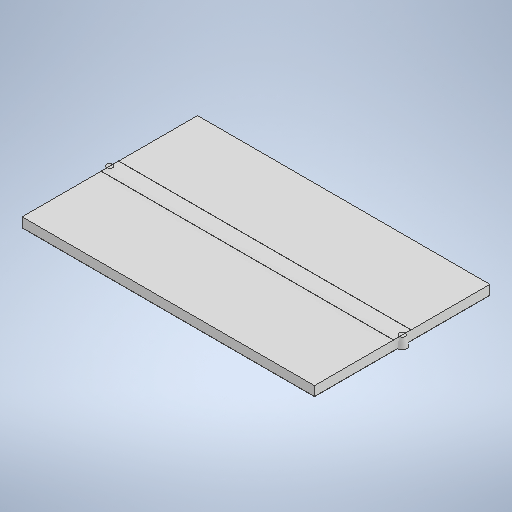
# Autodesk Inventor part: 01_linie50x30_3
Saved by Autodesk Inventor 2025.3 (Build 293356000, 356)
## iProperties
Created: 2026-10-16
Part Number: 01_linie50x30_3
Material: Generisch
Document SubType Name: Modeling
Designer: v.ivko
Density: 1 g/cm^3
Appearance: Vorgabe
Author: v.ivko
Autodesk Inventor part; units mm, degrees
ref_plane "YZ Plane" through (0, 0, 0) normal (1, 0, 0) x (0, 1, 0)
ref_plane "XZ Plane" through (0, 0, 0) normal (0, 1, 0) x (-1, 0, 0)
ref_plane "XY Plane" through (0, 0, 0) normal (0, 0, 1) x (1, 0, 0)
sketch "Skizze1" plane through (0, 0, 0) normal (0, 1, 0) x (-1, 0, 0)
  line L0 (-25, -15) -> (25, -15)
  line L1 (25, -15) -> (25, 15)
  line L2 (25, 15) -> (-25, 15)
  line L3 (-25, 15) -> (-25, -15)
  line L4 (-25, -15) -> (25, 15) construction
  line L5 (25, -15) -> (-25, 15) construction
  point P0 (0, 0)
  dimension "d0" = 50
  dimension "d1" = 30
  constraints: 12 end point, 2 midpoint, 2 parallel, 1 horizontal, 1 perpendicular
  measures "d0" distance of L1.end L2.end
  measures "d1" distance of L2.end L0.start
extrude "Extrusion1" add sketch "Skizze1" along normal blind 0.035
sketch "Skizze2" plane through (0, 0.035, 0) normal (0, 1, 0) x (1, 0, 0)
  line L0 (25, 15) -> (-25, 15) projected
  line L1 (25, -15) -> (-25, -15)
  line L2 (-25, -15) -> (-25, 15)
  line L3 (-25, 15) -> (25, 15)
  line L4 (25, 15) -> (25, -15)
  line L5 (25, -15) -> (-25, 15) construction
  line L6 (-25, -15) -> (25, 15) construction
  point P0 (0, 0)
  constraints: 12 end point, 2 midpoint, 2 parallel, 1 horizontal, 1 perpendicular
extrude "Extrusion2" add sketch "Skizze2" along normal blind 1.6 separate body
sketch "Skizze3" plane through (0, 1.635, 0) normal (0, 1, 0) x (1, 0, 0)
  line L0 (25, -1.5) -> (-25, -1.5)
  line L1 (-25, -1.5) -> (-25, 1.5)
  line L2 (-25, 1.5) -> (25, 1.5)
  line L3 (25, 1.5) -> (25, -1.5)
  line L4 (25, -1.5) -> (-25, 1.5) construction
  line L5 (-25, -1.5) -> (25, 1.5) construction
  point P0 (0, 0)
  dimension "d6" = 3
  dimension "d7" = 50
  constraints: 12 end point, 2 midpoint, 2 parallel, 1 horizontal, 1 perpendicular
  measures "d6" distance between parallel lines of L0 L2
  measures "d7" distance of L1.end L2.end
extrude "Extrusion3" add sketch "Skizze3" along normal blind 0.035 separate body
sketch "Skizze5" plane through (0, 1.67, 0) normal (0, 1, 0) x (1, 0, 0)
  line L0 (25, -15) -> (25, 15) projected
  circle A0 centre (25, 0) radius 0.5
  point P0 (0, 0)
  dimension "d12" = 1
  constraints: 1 centre point, 1 midpoint
  measures "d12" diameter of A0
extrude "Extrusion4" add sketch "Skizze5" against normal up to surface (1.67 mm away) draft 10 separate body
sketch "Skizze6" plane through (0, 1.67, 0) normal (0, 1, 0) x (1, 0, 0)
  line L0 (-25, 15) -> (-25, -15) projected
  circle A0 centre (-25, 0) radius 0.5
  point P0 (0, 0)
  dimension "d13" = 1
  constraints: 1 centre point, 1 midpoint
  measures "d13" diameter of A0
extrude "Extrusion5" add sketch "Skizze6" against normal up to surface (1.67 mm away) draft 10 separate body
